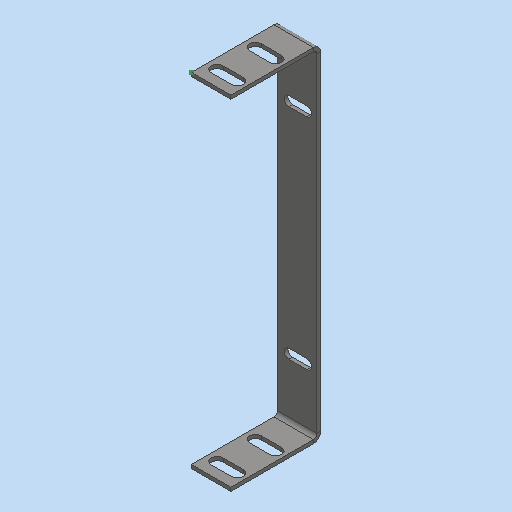
# Autodesk Inventor part: MM0861AN200_G22_110
Saved by Autodesk Inventor 2023.3 (Build 273359000, 359)
## iProperties
Part Number: MM0861AN200_G22_110
Material: 1.4301 X5CrNi18-10
Description: =<RBPARTNOTITLE2>
Document SubType Name: Blech
Designer: Benutzer
Mass: 300.518 g
Surface Area: 293.983 cm^2
Volume: 38.2825 cm^3
Density: 7.85 g/cm^3
Sheet Metal Rule: Standard_mm
Appearance: Stahl - rostfrei AnP
Vendor: ASW
Flat Pattern Width: 3.3 cm
Flat Pattern Length: 42.6572 cm
Flat Pattern Area: 140.769 cm^2
Sheet Metal Width: 33,000 mm
Sheet Metal Length: 426,572 mm
Sheet Metal Area: 14076,865 mm^2
RBCHANGEDESCRIPTION1: Erstfreigabe
RBCHANGENO1: 00
RBDOCUMENTTYPE: DRF
RBDOCUMENTVERSION: 00
RBDRAWINGMAINSCALE: 1:1
RBDRAWINGMISSINGSPEC: --
RBDRAWINGVOLUME: --
RBDSV1: 0850
RBGBDETAILS: 43274
RBGBEDGESIN1: +0,5
RBGBEDGESIN2: +0,2
RBGBEDGESOUT1: -0,3
RBGBEDGESOUT2: -0,1
RBMATERIAL: =<Material>
RBMATMEETS: --
RBMATNO: =<Part Number>
RBORGUNITRESPONSIBLE1: AnP/TEF1
RBPARTMADEOF: 287 x 75 x 33 (FM)
RBPARTNO: SIEHE MNR
RBPARTNOTITLE1: manufactured part
RBPARTNOTITLE2: Anfertigungsteil
RBPARTSAFETYINDICATOR: --
RBSURFACE: --
RBSURFACE2: --
RBZEDGESNORM: ISO13715:2002-06
RBZGENDIMCLASS: m
RBZGENDIMNORM: ISO 2768-1:1989-11
RBZGENGEOCLASS: H
RBZGENGEONORM: ISO 2768-2:1989-11
RBZSURFACENORM: ISO13D2:2002-02
RBZTOLERANCENORM: ISO 14405-1:2010-12
AnP_Material: =<Material>
AnP_TemplVers: 20190222
AnP_Kategorie: 1
MaxAbmaße: 287 x 75 x 33 (FM)
Author: Benutzer
Keywords: =<RBPARTMADEOF>
Comments: =<RBSURFACE2>
Revision Number: 01
Autodesk Inventor part; units mm, degrees
ref_plane "YZ Plane" through (0, 0, 0) normal (1, 0, 0) x (0, 1, 0)
ref_plane "XZ Plane" through (0, 0, 0) normal (0, 1, 0) x (-1, 0, 0)
ref_plane "XY Plane" through (0, 0, 0) normal (0, 0, 1) x (1, 0, 0)
sketch "Skizze1" plane through (0, 0, 0) normal (0, 0, 1) x (1, 0, 0)
  line L0 (0, 0) -> (33, 0)
  line L1 (33, 0) -> (33, 75)
  line L2 (33, 75) -> (0, 75)
  line L3 (0, 75) -> (0, 0)
  dimension "d0" = 33
  dimension "d1" = 75
  constraints: 8 end point, 2 parallel, 1 horizontal, 1 perpendicular
  measures "d0" distance of L2.end L1.end
  measures "d1" distance of L1.end L0.end
extrude "Extrusion1" add sketch "Skizze1" along normal blind 3
sketch "Skizze2" plane through (0, 72, 0) normal (0, 1, 0) x (-1, 0, 0)
  line L0 (-33, 0) -> (0, 0)
  line L1 (0, 0) -> (0, 287)
  line L2 (0, 287) -> (-33, 287)
  line L3 (-33, 287) -> (-33, 0)
  constraints: 4 end point, 4 other
edge flange "Lasche1" height 287 angle 90 thickness 3 bend radius 3 thickness toward (0, 1, 0) relief tear relief width 3 relief depth 1.5 edges at (16.5, 75, 3) wall of the first edge with corners at (33, 72, 0) (0, 72, 0) (0, 72, 287) (33, 72, 287)
bend "Biegung1"
corner "Ecke1"
sketch "Skizze4" plane through (0, 0, 3) normal (0, 0, 1) x (1, 0, 0)
  line L0 (25.5, 45) -> (8.5, 45) construction
  line L1 (25.5, 50) -> (8.5, 50)
  line L2 (8.5, 40) -> (25.5, 40)
  arc A0 (25.5, 40) -> (25.5, 50) centre (25.5, 45) ccw
  arc A1 (8.5, 50) -> (8.5, 40) centre (8.5, 45) ccw
  line L3 (25.5, 13) -> (8.5, 13) construction
  line L4 (25.5, 18) -> (8.5, 18)
  line L5 (8.5, 8) -> (25.5, 8)
  arc A2 (25.5, 8) -> (25.5, 18) centre (25.5, 13) ccw
  arc A3 (8.5, 18) -> (8.5, 8) centre (8.5, 13) ccw
  line L6 (33, 0) -> (33, 69) projected
  point P0 (0, 0)
  point P1 (17, 45)
  point P2 (17, 13)
  dimension "d20" = 17
  dimension "d21" = 10
  dimension "d22" = 10
  dimension "d23" = 16
  constraints: 16 end point, 8 point on circle, 8 tangent, 4 centre point, 3 parallel, 2 midpoint, 2 vertical alignment, 1 horizontal
  measures "d20" distance of L0.start L0.end
  measures "d21" diameter of A1
  measures "d22" diameter of A3
  measures "d23" distance from line of L6 point (17, 45)
extrude "Extrusion3" cut sketch "Skizze4" against normal through all
sketch "Skizze5" plane through (0, 72, 287) normal (0, -1, 0) x (1, 0, 0)
  line L0 (9.5, -235) -> (24.5, -235) construction
  line L1 (9.5, -239) -> (24.5, -239)
  line L2 (24.5, -231) -> (9.5, -231)
  arc A0 (9.5, -231) -> (9.5, -239) centre (9.5, -235) ccw
  arc A1 (24.5, -239) -> (24.5, -231) centre (24.5, -235) ccw
  line L3 (0, -287) -> (33, -287) projected
  line L4 (0, 0) -> (0, -281) projected
  point P0 (17, -235)
  dimension "d26" = 8
  dimension "d28" = 17
  dimension "d29" = 15
  dimension "d44" = 52
  constraints: 8 end point, 4 point on circle, 4 tangent, 2 centre point, 1 horizontal, 1 midpoint, 1 parallel
  measures "d26" diameter of A1
  measures "d28" distance from line of point (17, -235) L4
  measures "d29" distance of L0.end L0.start
  measures "d44" distance from line of point (17, -235) L3
extrude "Extrusion4" cut sketch "Skizze5" against normal blind 3
sketch "Skizze6" plane through (0, 75, 284) normal (0, 0, 1) x (1, 0, 0)
  line L0 (33, 0) -> (0, 0)
  line L1 (0, 0) -> (0, -75)
  line L2 (0, -75) -> (33, -75)
  line L3 (33, -75) -> (33, 0)
  constraints: 4 end point, 4 other
edge flange "Lasche2" height 75 angle 90 thickness 3 bend radius 3 thickness toward (0, 0, 1) relief tear relief width 3 relief depth 1.5 edges at (16.5, 72, 287) wall of the first edge with corners at (33, 75, 284) (0, 75, 284) (0, 0, 284) (33, 0, 284)
bend "Biegung2"
corner "Ecke2"
sketch "Skizze7" plane through (0, 0, 287) normal (0, 0, 1) x (1, 0, 0)
  point P0 (0, 0)
sketch "Skizze8" plane through (0, 0, 0) normal (0, 0, -1) x (-1, 0, 0)
  line L0 (-25.5, 18) -> (-8.5, 18) projected
  line L1 (-8.5, 8) -> (-25.5, 8) projected
  arc A0 (-8.5, 8) -> (-8.5, 18) centre (-8.5, 13) ccw projected
  arc A1 (-25.5, 18) -> (-25.5, 8) centre (-25.5, 13) ccw projected
  arc A2 (-8.5, 40) -> (-8.5, 50) centre (-8.5, 45) ccw projected
  line L2 (-8.5, 40) -> (-25.5, 40) projected
  line L3 (-25.5, 50) -> (-8.5, 50) projected
  arc A3 (-25.5, 50) -> (-25.5, 40) centre (-25.5, 45) ccw projected
  point P0 (0, 0)
extrude "Extrusion5" cut sketch "Skizze8" against normal through all
sketch "Skizze9" plane through (0, 72, 6) normal (0, -1, 0) x (1, 0, 0)
  line L0 (33, 275) -> (0, 275) projected
  line L1 (0, 275) -> (0, 0) projected
  line L2 (0, 0) -> (33, 0) projected
  line L3 (33, 275) -> (33, 0) projected
  arc A0 (24.5, 42) -> (24.5, 50) centre (24.5, 46) ccw projected
  line L4 (24.5, 42) -> (9.5, 42) projected
  arc A1 (9.5, 50) -> (9.5, 42) centre (9.5, 46) ccw projected
  line L5 (9.5, 50) -> (24.5, 50) projected
  line L6 (24.5, 229) -> (9.5, 229) construction
  line L7 (24.5, 233) -> (9.5, 233)
  line L8 (9.5, 225) -> (24.5, 225)
  arc A2 (24.5, 225) -> (24.5, 233) centre (24.5, 229) ccw
  arc A3 (9.5, 233) -> (9.5, 225) centre (9.5, 229) ccw
  line L9 (33, 281) -> (0, 281) projected
  point P0 (0, -6)
  point P1 (17, 229)
  dimension "d45" = 8
  dimension "d46" = 52
  constraints: 8 end point, 4 point on circle, 4 tangent, 2 centre point, 2 vertical alignment, 1 horizontal, 1 midpoint, 1 parallel
  measures "d45" diameter of A3
  measures "d46" distance from line of point (17, 229) L9
extrude "Extrusion6" cut sketch "Skizze9" against normal blind 10 contours A2 L8 A3 L7
equation "\"d4\" = BreiteBiegungsfreistellung"
equation "\"d5\" = TiefeBiegungsfreistellung"
equation "\"d6\" = MinimalRest"
equation "\"d7\" = Biegeradius"
equation "\"d10\" = Biegeradius"
equation "\"d11\" = GrößeEckenfreistellung"
equation "\"d12\" = Abstandsgröße"
equation "\"d13\" = JacobiRadiusGröße"
equation "\"d49\" = Stärke"
equation "\"d32\" = BreiteBiegungsfreistellung"
equation "\"d33\" = TiefeBiegungsfreistellung"
equation "\"d34\" = MinimalRest"
equation "\"d35\" = Biegeradius"
equation "\"d38\" = Biegeradius"
equation "\"d39\" = GrößeEckenfreistellung"
equation "\"d40\" = Abstandsgröße"
equation "\"d41\" = JacobiRadiusGröße"
equation "\"Biegeradius\" = Stärke"
equation "\"BreiteBiegungsfreistellung\" = Stärke"
equation "\"TiefeBiegungsfreistellung\" = 0.5 * Stärke"
equation "\"GrößeEckenfreistellung\" = 4 * Stärke"
equation "\"MinimalRest\" = 2 * Stärke"
equation "\"Übergangsradius\" = Biegeradius"
equation "\"JacobiRadiusGröße\" = Biegeradius"
equation "\"Abstandsgröße\" = Stärke"
equation "\"Stärke\" = 3"
